Autodesk Fusion 360 part; units mm, degrees
(part 3 of 3)
sketch "Sketch19" plane through (0, 0, 12.7) normal (0, 0, 1) x (-1, 0, 0)
  arc A0 (-64.8606, -8.4023) -> (-38.1, -0.7823) centre (-64.8606, 42.3977) ccw
  line L0 (-64.8606, -8.4023) -> (-129.8626, -8.4023)
  line L1 (-152.4, -3.1293) -> (-190.5, -3.9116)
  line L2 (-190.5, -3.9116) -> (-190.5, -10.1919)
  line L3 (-190.5, -10.1919) -> (-185.4208, -15.2712)
  line L4 (-190.4286, -15.3406) -> (-190.0185, -44.9186)
  line L5 (-190.0185, -44.9186) -> (-108.0263, -43.7816)
  line L6 (-108.0263, -43.7816) -> (-108.0704, -40.607)
  arc A1 (-98.6791, -14.0683) -> (-108.3731, -18.7752) centre (-98.503, -26.7671) ccw
  line L7 (-98.6791, -14.0683) -> (0, -12.7)
  line L8 (0, -12.7) -> (0, 0)
  line L9 (0, 0) -> (-38.1, -0.7823)
  line L10 (-38.1, 0) -> (0, 0)
  line L11 (0, 0) -> (0, -12.7)
  line L12 (0, -12.7) -> (-38.1, -12.7)
  line L13 (-38.1, -12.7) -> (-38.1, 0)
  line L14 (-108.0704, -40.607) -> (-115.6896, -40.7126)
  line L15 (-115.6896, -40.7126) -> (-115.6911, -40.6066)
  line L16 (-115.6911, -40.6066) -> (-188.431, -40.6066)
  line L17 (-188.431, -40.6066) -> (-188.431, -18.6066)
  line L18 (-188.431, -18.6066) -> (-111.2013, -18.6066)
  line L19 (-111.2013, -18.6066) -> (-111.2013, -18.8144)
  line L20 (-111.2013, -18.8144) -> (-108.3731, -18.7752)
  arc A2 (-152.4, -3.1293) -> (-129.8626, -8.4023) centre (-129.8626, 42.3977) ccw
  line L21 (-185.4208, -15.2712) -> (-190.4286, -15.3406)
  constraint horizontal L10
  constraint vertical L11
  constraint horizontal L12
  constraint vertical L13
  constraint coincident L7.end L8.start
  constraint vertical A0.end L10.start
  constraint coincident L8.end L9.start
extrude "Extrude13" add sketch "Sketch19" against normal blind 12.7 contours L9 L10 L13 bodies 1
sketch "Sketch20" plane through (0, 0, 12.7) normal (0, 0, 1) x (-1, 0, 0)
  arc A0 (-64.8606, -8.4023) -> (-38.1, -0.7823) centre (-64.8606, 42.3977) ccw
  line L0 (-64.8606, -8.4023) -> (-129.8626, -8.4023)
  line L1 (-152.4, -3.1293) -> (-190.5, -3.9116)
  line L2 (-190.5, -3.9116) -> (-190.5, -10.1919)
  line L3 (-190.5, -10.1919) -> (-185.4208, -15.2712)
  line L4 (-190.4286, -15.3406) -> (-190.0185, -44.9186)
  line L5 (-190.0185, -44.9186) -> (-108.0263, -43.7816)
  line L6 (-108.0263, -43.7816) -> (-108.0704, -40.607)
  arc A1 (-98.6791, -14.0683) -> (-108.3731, -18.7752) centre (-98.503, -26.7671) ccw
  line L7 (-98.6791, -14.0683) -> (0, -12.7)
  line L8 (0, -12.7) -> (0, 0)
  line L9 (0, 0) -> (-38.1, 0)
  line L10 (-38.1, 0) -> (-38.1, -0.7823)
  line L11 (-108.0263, -43.7816) -> (-108.0484, -42.1943)
  line L12 (-108.0263, -43.7816) -> (-118.1863, -43.9225)
  line L13 (-118.1794, -40.6718) -> (-103.7202, -40.7025)
  line L14 (-103.7202, -40.7025) -> (-103.7202, -42.2014)
  line L15 (-108.0484, -42.1943) -> (-103.7202, -42.2014)
  line L16 (-118.1863, -43.9225) -> (-118.1794, -40.6718)
  line L17 (-190.0185, -44.9186) -> (-190.2235, -30.1296)
  line L18 (-180.6322, -30.1296) -> (-190.2235, -30.1296)
  line L19 (-180.6322, -30.1296) -> (-180.6322, -40.7657)
  line L20 (-180.6322, -40.7657) -> (-179.8077, -40.7657)
  line L21 (-179.8585, -44.7777) -> (-179.8077, -40.7657)
  line L22 (-179.8585, -44.7777) -> (-190.0185, -44.9186)
  line L23 (-153.3272, -18.2577) -> (-166.0272, -18.2577)
  line L24 (-166.0272, -18.2577) -> (-166.0272, -15.7177)
  line L25 (-166.0272, -15.7177) -> (-153.3272, -15.7177)
  line L26 (-153.3272, -15.7177) -> (-153.3272, -18.2577)
  line L27 (-108.0704, -40.607) -> (-115.6896, -40.7126)
  line L28 (-115.6896, -40.7126) -> (-115.6911, -40.6066)
  line L29 (-115.6911, -40.6066) -> (-188.431, -40.6066)
  line L30 (-188.431, -40.6066) -> (-188.431, -18.6066)
  line L31 (-188.431, -18.6066) -> (-111.2013, -18.6066)
  line L32 (-111.2013, -18.6066) -> (-111.2013, -18.8144)
  line L33 (-111.2013, -18.8144) -> (-108.3731, -18.7752)
  arc A2 (-152.4, -3.1293) -> (-129.8626, -8.4023) centre (-129.8626, 42.3977) ccw
  line L34 (-185.4208, -15.2712) -> (-190.4286, -15.3406)
  dimension "d98" = 10.16
  dimension "d99" = 10.16
  dimension "d102" = 2.54
  dimension "d103" = 12.7
  constraint coincident L5.end L6.start
  constraint midpoint L6 L11.end
  constraint coincident L5 L12.end
  constraint coincident L6 L11.end
  constraint perpendicular L13 L16
  constraint coincident L11.end L15.start
  constraint coincident L4.end L5.start
  constraint midpoint L4 L17.end
  constraint horizontal L18
  constraint coincident L5 L21.start
  constraint horizontal L23
  constraint vertical L24
  constraint horizontal L25
  constraint vertical L26
  measures "d98" horizontal distance of L5.end L12.end
  measures "d99" horizontal distance of L4.end L21.start
  measures "d102" distance of L23.start L25.end
  measures "d103" distance of L24.end L25.end
sketch "Sketch21" plane through (0, 0, 12.7) normal (0, 0, 1) x (-1, 0, 0)
  line L0 (-108.0263, -43.7816) -> (-108.0704, -40.607)
  arc A0 (-98.6791, -14.0683) -> (-108.3731, -18.7752) centre (-98.503, -26.7671) ccw
  line L1 (-98.6791, -14.0683) -> (0, -12.7)
  line L2 (0, -12.7) -> (0, 0)
  line L3 (0, 0) -> (-38.1, 0)
  line L4 (-38.1, 0) -> (-38.1, -0.7823)
  arc A1 (-64.8606, -8.4023) -> (-38.1, -0.7823) centre (-64.8606, 42.3977) ccw
  line L5 (-64.8606, -8.4023) -> (-129.8626, -8.4023)
  line L6 (-152.4, -3.1293) -> (-190.5, -3.9116)
  line L7 (-190.5, -3.9116) -> (-190.5, -10.1919)
  line L8 (-190.5, -10.1919) -> (-185.4208, -15.2712)
  line L9 (-190.4286, -15.3406) -> (-190.0185, -44.9186)
  line L10 (0, 0) -> (-38.1, 0)
  line L11 (-38.1, 0) -> (-38.1, -4.699)
  line L12 (-38.1, -4.699) -> (0, -4.699)
  line L13 (0, -4.699) -> (0, 0)
  line L14 (-38.1, -4.699) -> (-46.3813, -4.699)
  line L15 (-46.3813, -4.699) -> (-46.3813, 0)
  line L16 (-46.3813, 0) -> (-38.1, 0)
  line L17 (-38.1, 0) -> (-38.1, -4.699)
  line L18 (-190.0185, -44.9186) -> (-108.0263, -43.7816)
  line L19 (-108.0704, -40.607) -> (-115.6896, -40.7126)
  line L20 (-115.6896, -40.7126) -> (-115.6911, -40.6066)
  line L21 (-115.6911, -40.6066) -> (-188.431, -40.6066)
  line L22 (-188.431, -40.6066) -> (-188.431, -18.6066)
  line L23 (-188.431, -18.6066) -> (-111.2013, -18.6066)
  line L24 (-111.2013, -18.6066) -> (-111.2013, -18.8144)
  line L25 (-111.2013, -18.8144) -> (-108.3731, -18.7752)
  arc A2 (-152.4, -3.1293) -> (-129.8626, -8.4023) centre (-129.8626, 42.3977) ccw
  line L26 (-185.4208, -15.2712) -> (-190.4286, -15.3406)
  dimension "d105" = 8.001
  dimension "d106" = 8.2813
  constraint horizontal L10
  constraint vertical L11
  constraint horizontal L12
  constraint vertical L13
  constraint coincident L2.end L3.start
  constraint coincident L3.end L4.start
  constraint horizontal L14
  constraint vertical L15
  constraint horizontal L16
  constraint vertical L17
  measures "d105" distance of L1.end L12
  measures "d106" distance of L15.end L3.end
extrude "Extrude15" cut sketch "Sketch21" against normal blind 12.7 contours L4 A1 L11 L14 L15 L16 L17 | A1 L11 L14 L17 | L2 L3 L4 L10 L11 L12 L13 L17 bodies 1
sketch "Sketch23" plane through (0, 0, 12.7) normal (0, 0, 1) x (-1, 0, 0)
  line L0 (0, -4.699) -> (-45.82, -4.699)
  arc A0 (-64.8606, -8.4023) -> (-45.82, -4.699) centre (-64.8606, 42.3977) ccw
  line L1 (-64.8606, -8.4023) -> (-129.8626, -8.4023)
  arc A1 (-152.4, -3.1293) -> (-129.8626, -8.4023) centre (-129.8626, 42.3977) ccw
  line L2 (-152.4, -3.1293) -> (-190.5, -3.9116)
  line L3 (-190.5, -3.9116) -> (-190.5, -10.1919)
  line L4 (-190.5, -10.1919) -> (-185.4208, -15.2712)
  line L5 (-190.4286, -15.3406) -> (-190.0185, -44.9186)
  line L6 (-190.0185, -44.9186) -> (-108.0263, -43.7816)
  line L7 (-108.0263, -43.7816) -> (-108.0704, -40.607)
  line L8 (-108.0704, -40.607) -> (-115.6896, -40.7126)
  line L9 (-115.6896, -40.7126) -> (-115.6911, -40.6066)
  line L10 (-115.6911, -40.6066) -> (-188.431, -40.6066)
  line L11 (-188.431, -40.6066) -> (-188.431, -18.6066)
  line L12 (-188.431, -18.6066) -> (-111.2013, -18.6066)
  line L13 (-111.2013, -18.6066) -> (-111.2013, -18.8144)
  line L14 (-111.2013, -18.8144) -> (-108.3731, -18.7752)
  arc A2 (-98.6791, -14.0683) -> (-108.3731, -18.7752) centre (-98.503, -26.7671) ccw
  line L15 (-98.6791, -14.0683) -> (0, -12.7)
  line L16 (0, -12.7) -> (0, -4.699)
  line L17 (-188.431, -18.6066) -> (-108.0704, -18.6066)
  line L18 (-108.0704, -18.6066) -> (-108.0704, -40.607)
  line L19 (-108.0704, -40.607) -> (-188.431, -40.607)
  line L20 (-188.431, -40.607) -> (-188.431, -18.6066)
  line L21 (-185.4208, -15.2712) -> (-190.4286, -15.3406)
  constraint horizontal L17
  constraint vertical L18
  constraint horizontal L19
  constraint vertical L20
  constraint coincident L7.end L8.start
  constraint coincident L11.end L12.start
extrude "Extrude18" add 1 faces at (187.09, 15.2943, 4.2333) along direction (0.013865, -0.999904, 0) blind 11.43 on bodies 1 bodies 1
sketch "Sketch24" plane through (0, 0, 12.7) normal (0, 0, 1) x (-1, 0, 0)
  line L0 (-190.5871, -3.9117) -> (-190.0185, -44.9186)
  line L1 (-190.0185, -44.9186) -> (-108.0263, -43.7816)
  line L2 (-108.0263, -43.7816) -> (-108.0704, -40.607)
  line L3 (-108.0704, -40.607) -> (-115.6896, -40.7126)
  line L4 (-115.6896, -40.7126) -> (-115.6911, -40.6066)
  line L5 (-115.6911, -40.6066) -> (-188.431, -40.6066)
  line L6 (-188.431, -40.6066) -> (-188.431, -18.6066)
  line L7 (-188.431, -18.6066) -> (-111.2013, -18.6066)
  line L8 (-111.2013, -18.6066) -> (-111.2013, -18.8144)
  line L9 (-111.2013, -18.8144) -> (-108.3731, -18.7752)
  arc A0 (-98.6791, -14.0683) -> (-108.3731, -18.7752) centre (-98.503, -26.7671) ccw
  line L10 (-98.6791, -14.0683) -> (0, -12.7)
  line L11 (0, -12.7) -> (0, -4.699)
  line L12 (0, -4.699) -> (-45.82, -4.699)
  arc A1 (-64.8606, -8.4023) -> (-45.82, -4.699) centre (-64.8606, 42.3977) ccw
  line L13 (-64.8606, -8.4023) -> (-129.8626, -8.4023)
  arc A2 (-152.4, -3.1293) -> (-129.8626, -8.4023) centre (-129.8626, 42.3977) ccw
  line L14 (-152.4, -3.1293) -> (-190.3352, -3.9082)
  line L15 (-190.3352, -3.9082) -> (-190.5871, -3.9117)
  line L16 (-105.918, 5) -> (-46.99, 5)
  line L17 (-46.99, 5) -> (-46.99, -30)
  line L18 (-46.99, -30) -> (-105.918, -30)
  line L19 (-105.918, -30) -> (-105.918, 5)
  dimension "d120" = 46.99
  dimension "d121" = 58.928
  dimension "d122" = 35
  dimension "d123" = 17.7
  constraint horizontal L16
  constraint vertical L17
  constraint horizontal L18
  constraint vertical L19
  measures "d120" distance of L11 L17
  measures "d121" distance of L17.end L18.end
  measures "d122" distance of L16.end L17.end
  measures "d123" vertical distance of L10.end L16.end
extrude "Extrude19" cut sketch "Sketch24" against normal blind 8.89 contours A0 L10 A1 L13 L17 L19 bodies 1
sketch "Sketch25" plane through (-0.1761, 12.6976, 0) normal (-0.013865, 0.999904, 0) x (-0.999904, -0.013865, 0)
  line L0 (-47.1706, 12.7) -> (-47.1706, 3.81)
  line L1 (-47.1706, 3.81) -> (-98.8646, 3.81)
  line L2 (-98.8646, 3.81) -> (-98.8646, 0)
  line L3 (-98.8646, 0) -> (-0.1761, 0)
  line L4 (-0.1761, 0) -> (-0.1761, 12.7)
  line L5 (-0.1761, 12.7) -> (-47.1706, 12.7)
  line L6 (-106.0986, 3.81) -> (-47.1706, 3.81)
  line L7 (-47.1706, 3.81) -> (-47.1706, 0)
  line L8 (-47.1706, 0) -> (-106.0986, 0)
  line L9 (-106.0986, 0) -> (-106.0986, 3.81)
  line L10 (-93.3986, 3.81) -> (-83.8736, 3.81)
  line L11 (-83.8736, 3.81) -> (-83.8736, 0)
  line L12 (-83.8736, 0) -> (-93.3986, 0)
  line L13 (-93.3986, 0) -> (-93.3986, 3.81)
  line L14 (-69.3956, 3.81) -> (-59.8706, 3.81)
  line L15 (-59.8706, 3.81) -> (-59.8706, 0)
  line L16 (-59.8706, 0) -> (-69.3956, 0)
  line L17 (-69.3956, 0) -> (-69.3956, 3.81)
  dimension "d126" = 58.928
  dimension "d127" = 12.7
  dimension "d128" = 12.7
  dimension "d129" = 9.525
  dimension "d130" = 9.525
  constraint horizontal L6
  constraint vertical L7
  constraint horizontal L8
  constraint vertical L9
  constraint coincident L3 L7.end
  constraint coincident L0.end L1.start
  constraint horizontal L10
  constraint vertical L11
  constraint horizontal L12
  constraint vertical L13
  constraint coincident L8 L11.end
  constraint coincident L6 L10.start
  constraint horizontal L14
  constraint vertical L15
  constraint horizontal L16
  constraint vertical L17
  constraint coincident L8 L15.end
  constraint coincident L6 L14.start
  measures "d126" distance of L6.start L0.end
  measures "d127" distance of L9 L13
  measures "d128" distance of L7 L15
  measures "d129" distance of L11.end L13
  measures "d130" distance of L15 L17
extrude "Extrude20" add sketch "Sketch25" along normal blind 30.2133 contours L1 L3 L6 L8 L14 L15 L16 L17 | L1 L3 L6 L8 L10 L11 L12 L13 bodies 1
sketch "Sketch26" plane through (0, 0, 3.81) normal (0, 0, 1) x (-1, 0, 0)
  line L0 (-64.8606, -8.4023) -> (-105.918, -8.4023)
  line L1 (-105.918, -8.4023) -> (-105.918, -16.4566)
  arc A0 (-98.6791, -14.0683) -> (-105.918, -16.4566) centre (-98.503, -26.7671) ccw
  line L2 (-98.6791, -14.0683) -> (-93.2136, -13.9926)
  line L3 (-93.2136, -13.9926) -> (-92.7946, -44.203)
  line L4 (-92.7946, -44.203) -> (-83.2706, -44.0709)
  line L5 (-83.2706, -44.0709) -> (-83.6895, -13.8605)
  line L6 (-83.6895, -13.8605) -> (-69.2129, -13.6598)
  line L7 (-69.2129, -13.6598) -> (-68.7939, -43.8701)
  line L8 (-68.7939, -43.8701) -> (-59.2699, -43.7381)
  line L9 (-59.2699, -43.7381) -> (-59.6888, -13.5277)
  line L10 (-59.6888, -13.5277) -> (-46.99, -13.3516)
  line L11 (-46.99, -13.3516) -> (-46.99, -5.1553)
  arc A1 (-64.8606, -8.4023) -> (-46.99, -5.1553) centre (-64.8606, 42.3977) ccw
  line L12 (-83.2706, -44.0709) -> (-92.7965, -44.0709)
  line L13 (-92.7965, -44.0709) -> (-92.7965, -42.4834)
  line L14 (-92.7965, -42.4834) -> (-83.2706, -42.4834)
  line L15 (-83.2706, -42.4834) -> (-83.2706, -44.0709)
  line L16 (-59.2699, -43.7381) -> (-68.8178, -43.7381)
  line L17 (-68.8178, -43.7381) -> (-68.8178, -42.1506)
  line L18 (-68.8178, -42.1506) -> (-59.2699, -42.1506)
  line L19 (-59.2699, -42.1506) -> (-59.2699, -43.7381)
  dimension "d133" = 1.5875
  dimension "d134" = 1.5875
  constraint horizontal L12
  constraint vertical L13
  constraint horizontal L14
  constraint vertical L15
  constraint coincident L4.end L5.start
  constraint horizontal L16
  constraint vertical L17
  constraint horizontal L18
  constraint vertical L19
  constraint coincident L7 L17.end
  constraint coincident L8.end L9.start
  constraint coincident L3 L12.end
  measures "d133" distance of L16 L18
  measures "d134" distance of L12 L14
extrude "Extrude21" add sketch "Sketch26" along normal blind 16.002 contours L7 L9 L16 L18 | L5 L12 L13 L14 bodies 1
extrude "Extrude22" add 1 faces at (30.9367, 10.2502, 12.7) along direction (0, 0, 1) blind 22.225 on bodies 1 bodies 1
sketch "Sketch27" plane through (0, 44.0709, 0) normal (0, 1, 0) x (-1, 0, 0)
  line L0 (-92.7965, 3.81) -> (-83.2706, 3.81)
  line L1 (-83.2706, 3.81) -> (-83.2706, 19.812)
  line L2 (-83.2706, 19.812) -> (-92.7965, 19.812)
  line L3 (-92.7965, 19.812) -> (-92.7965, 3.81)
  line L4 (-92.7965, 19.812) -> (-83.2706, 19.812)
  line L5 (-83.2706, 19.812) -> (-83.2706, 0)
  line L6 (-83.2706, 0) -> (-92.7965, 0)
  line L7 (-92.7965, 0) -> (-92.7965, 19.812)
  line L8 (-68.8178, 19.812) -> (-59.2699, 19.812)
  line L9 (-59.2699, 19.812) -> (-59.2699, 0)
  line L10 (-59.2699, 0) -> (-68.8178, 0)
  line L11 (-68.8178, 0) -> (-68.8178, 19.812)
  point P0 (-68.8178, 19.812)
  point P1 (-59.2699, 0)
  point P2 (-83.2706, 0)
  constraint horizontal L4
  constraint vertical L5
  constraint horizontal L6
  constraint vertical L7
  constraint coincident L2.end L3.start
  constraint horizontal L8
  constraint vertical L9
  constraint horizontal L10
  constraint vertical L11
  constraint coincident P0 L8.start
  constraint coincident P1 L9.end
  constraint coincident P2 L5.end
extrude "Extrude23" add sketch "Sketch27" along normal blind 1.5875 bodies 1 makes body 2 at (65.6351, 44.0709, 6.604)
extrude "Extrude24" add 1 faces at (65.6351, 44.0709, 6.604) along direction (0, -1, 0) blind 1.9304 on bodies 2 bodies 1 2
sketch "Sketch28" plane through (-0.1761, 12.6976, 0) normal (-0.013865, 0.999904, 0) x (-0.999904, -0.013865, 0)
  line L0 (-59.8706, 3.81) -> (-59.8706, 0)
  line L1 (-59.8706, 0) -> (-0.1761, 0)
  line L2 (-0.1761, 0) -> (-0.1761, 34.925)
  line L3 (-0.1761, 34.925) -> (-47.1706, 34.925)
  line L4 (-47.1706, 34.925) -> (-47.1706, 3.81)
  line L5 (-47.1706, 3.81) -> (-59.8706, 3.81)
  line L6 (-40.8206, 29.845) -> (-28.1206, 29.845)
  line L7 (-28.1206, 29.845) -> (-28.1206, 3.81)
  line L8 (-28.1206, 3.81) -> (-40.8206, 3.81)
  line L9 (-40.8206, 3.81) -> (-40.8206, 29.845)
  line L10 (-20.5006, 29.845) -> (-6.5261, 29.845)
  line L11 (-6.5261, 29.845) -> (-6.5261, 3.81)
  line L12 (-6.5261, 3.81) -> (-20.5006, 3.81)
  line L13 (-20.5006, 3.81) -> (-20.5006, 29.845)
  dimension "d143" = 7.62
  dimension "d144" = 6.35
  dimension "d145" = 6.35
  dimension "d146" = 5.08
  dimension "d147" = 12.7
  constraint horizontal L6
  constraint vertical L7
  constraint horizontal L8
  constraint vertical L9
  constraint horizontal L10
  constraint vertical L11
  constraint horizontal L12
  constraint vertical L13
  constraint horizontal L4.end L8.end
  constraint horizontal L4.end L12.end
  constraint horizontal L6.end L10.start
  measures "d143" distance of L7 L13
  measures "d144" distance of L2 L11
  measures "d145" distance of L4 L9
  measures "d146" distance of L3 L6
  measures "d147" distance of L7 L9
extrude "Extrude25" cut sketch "Sketch28" against normal blind 22.86 contours L6 L7 L8 L9 | L10 L11 L12 L13 bodies 1
fillet "Fillet7" radius 6.35 8 edges at (28, 8.8932, 29.845) (40.7, 8.9813, 29.845) (20.38, 8.8404, 29.845) (6.4055, 8.7435, 29.845) (6.4055, 8.7435, 3.81) (20.38, 8.8404, 3.81) (40.7, 8.9813, 3.81) (28, 8.8932, 3.81) on bodies 1
equation "d23 = ( 1 / 16 ) * 1 in"
equation "d129 = ( 3 / 8 ) * 1 in"
equation "d130 = ( 3 / 8 ) * 1 in"
equation "d131 = 1.127 in + ( 1 / 16 ) * 1 in"
equation "d133 = ( 1 / 16 ) * 1 in"
equation "d134 = ( 1 / 16 ) * 1 in"
equation "d139 = ( 1 / 16 ) * 1 in"
